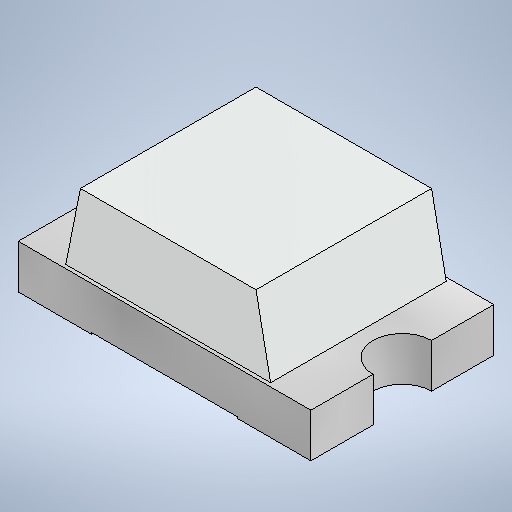
# Autodesk Inventor part: KT-0805G
Saved by Autodesk Inventor 2025.2 (Build 292293000, 293)
## iProperties
Created: 2025-06-22
Part Number: KT-0805G
Material: Generic
Document SubType Name: Modeling
Designer: K. Paulsen
Density: 1 g/cm^3
Appearance: Default
Author: K. Paulsen
Autodesk Inventor part; units mm, degrees
ref_plane "YZ Plane" through (0, 0, 0) normal (1, 0, 0) x (0, 1, 0)
ref_plane "XZ Plane" through (0, 0, 0) normal (0, 1, 0) x (-1, 0, 0)
ref_plane "XY Plane" through (0, 0, 0) normal (0, 0, 1) x (1, 0, 0)
sketch "Sketch1" plane through (0, 0, 0) normal (0, 1, 0) x (-1, 0, 0)
  line L0 (-1, -0.625) -> (1, -0.625)
  line L1 (1, -0.625) -> (1, 0.625)
  line L2 (1, 0.625) -> (-1, 0.625)
  line L3 (-1, 0.625) -> (-1, -0.625)
  line L4 (-1, -0.625) -> (1, 0.625) construction
  line L5 (1, -0.625) -> (-1, 0.625) construction
  point P0 (0, 0)
  dimension "d0" = 2
  dimension "d1" = 1.25
  constraints: 12 end point, 2 midpoint, 2 parallel, 1 horizontal, 1 perpendicular
  measures "d0" distance of L2.end L1.end
  measures "d1" distance of L1.end L0.end
extrude "Extrusion1" add sketch "Sketch1" along normal blind 0.3
sketch "Sketch2" plane through (0, 0, 0) normal (0, 0, 1) x (1, 0, 0)
  line L0 (-1, 0.3) -> (1, 0.3) projected
  line L1 (-0.7, 0.3) -> (-0.6, 0.8)
  line L2 (-0.6, 0.8) -> (0.6, 0.8)
  line L3 (0.6, 0.8) -> (0.7, 0.3)
  line L4 (1, 0.3) -> (-1, 0.3) projected
  line L5 (1, 0) -> (-1, 0) projected
  line L6 (0, 0) -> (0, 0.3) construction
  dimension "d4" = 1.4
  dimension "d5" = 1.2
  dimension "d6" = 0.8
  constraints: 8 end point, 2 point on line, 1 horizontal, 1 midpoint, 1 other
  measures "d4" distance of L3.end L1.start
  measures "d5" distance of L1.end L2.end
  measures "d6" distance between parallel lines of L5 L2
extrude "Extrusion2" add sketch "Sketch2" along normal mid plane 1.2
sketch "Sketch3" plane through (0, 0.3, 0) normal (0, 1, 0) x (1, 0, 0)
  line L0 (-1, 0.625) -> (-1, -0.625) projected
  circle A0 centre (-1, 0) radius 0.2
  line L1 (1, -0.625) -> (1, 0.625) projected
  circle A1 centre (1, 0) radius 0.2
  point P0 (0, 0)
  dimension "d9" = 0.4
  dimension "d10" = 0.4
  constraints: 2 centre point, 2 midpoint
  measures "d9" diameter of A0
  measures "d10" diameter of A1
extrude "Extrusion3" cut sketch "Sketch3" against normal through all
sketch "Sketch4" plane through (0, 0, 0) normal (0, -1, 0) x (1, 0, 0)
  line L0 (0.5, -0.6279) -> (-0.5, -0.6279)
  line L1 (-0.5, -0.6279) -> (-0.5, 0.6279)
  line L2 (-0.5, 0.6279) -> (0.5, 0.6279)
  line L3 (0.5, 0.6279) -> (0.5, -0.6279)
  line L4 (0.5, -0.6279) -> (-0.5, 0.6279) construction
  line L5 (-0.5, -0.6279) -> (0.5, 0.6279) construction
  line L6 (-1, 0.2) -> (-1, 0.625) projected
  point P0 (0, 0)
  dimension "d13" = 0.5
  constraints: 12 end point, 2 midpoint, 2 parallel, 1 horizontal, 1 perpendicular
  measures "d13" distance between parallel lines of L6 L1
extrude "Extrusion4" cut sketch "Sketch4" against normal blind 0.01
body "Solid1"
